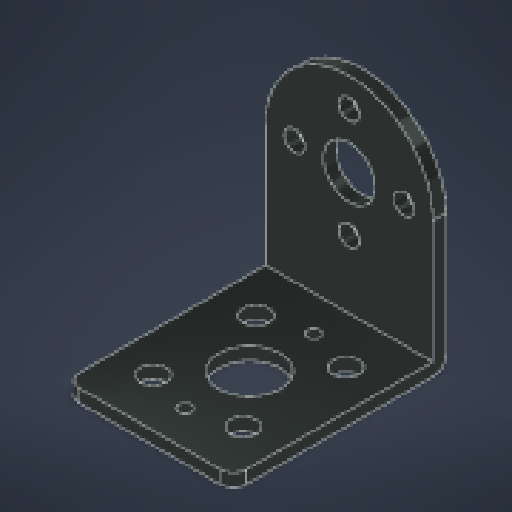
# Autodesk Inventor part: motor holder
Saved by Autodesk Inventor 2026.1 (Build 301233020, 233B)
## iProperties
Created: 2026-02-16
Part Number: motor holder
Material: Steel, Carbon
Document SubType Name: Modeling
Designer: Omar Kashef
Density: 7.85 g/cm^3
Appearance: Gunmetal - Polished
Author: Omar Kashef
Autodesk Inventor part; units mm, degrees
ref_plane "YZ Plane" through (0, 0, 0) normal (1, 0, 0) x (0, 1, 0)
ref_plane "XZ Plane" through (0, 0, 0) normal (0, 1, 0) x (-1, 0, 0)
ref_plane "XY Plane" through (0, 0, 0) normal (0, 0, 1) x (1, 0, 0)
sketch "Sketch1" plane through (0, 0, 0) normal (0, 1, 0) x (-1, 0, 0)
  line L0 (13, 15.5) -> (-13, 15.5)
  line L1 (-13, 15.5) -> (-13, -15.5)
  line L2 (-13, -15.5) -> (13, -15.5)
  line L3 (13, -15.5) -> (13, 15.5)
  line L4 (13, 15.5) -> (-13, -15.5) construction
  line L5 (-13, 15.5) -> (13, -15.5) construction
  circle A0 centre (0, 0) radius 4.8
  line L6 (13, -15.5) -> (-13, -15.5)
  line L7 (-13, -15.5) -> (-13, -17.5)
  line L8 (-13, -17.5) -> (13, -17.5)
  line L9 (13, -17.5) -> (13, -15.5)
  line L10 (-7, 8) -> (7, 8) construction
  line L11 (7, 8) -> (7, -8) construction
  line L12 (7, -8) -> (-7, -8) construction
  line L13 (-7, -8) -> (-7, 8) construction
  line L14 (-7, 8) -> (7, -8) construction
  line L15 (7, 8) -> (-7, -8) construction
  circle A1 centre (7, 8) radius 2
  circle A2 centre (7, -8) radius 2
  circle A3 centre (-7, -8) radius 2
  circle A4 centre (-7, 8) radius 2
  line L16 (0, 0) -> (0, 10) construction
  circle A5 centre (0, 10) radius 1
  line L17 (0, 0) -> (5.5, 0) construction
  circle A6 centre (0, -10) radius 1
  dimension "d0" = 26
  dimension "d1" = 31
  dimension "d2" = 9.6
  dimension "d3" = 15.5
  dimension "d4" = 2
  dimension "d5" = 26
  dimension "d6" = 14
  dimension "d7" = 16
  dimension "d8" = 4
  dimension "d9" = 2
  dimension "d10" = 10
  constraints: 36 end point, 7 centre point, 6 coincident, 6 parallel, 4 horizontal, 4 midpoint, 4 perpendicular, 3 equal radius, 1 symmetric about line, 1 other
  measures "d0" distance of L2.end L1.end
  measures "d1" distance of L1.end L0.end
  measures "d2" diameter of A0
  measures "d3" distance from line of L2 L16.start
  measures "d4" distance of L7.end L6.end
  measures "d5" distance of L7.end L8.end
  measures "d6" distance of L11.end L12.end
  measures "d7" distance of L10.end L11.end
  measures "d8" diameter of A1
  measures "d9" diameter of A5
  measures "d10" distance of L16.start L16.end
extrude "Extrusion1" add sketch "Sketch1" along normal blind 2 contours L3 L2 L1 L0
extrude "Extrusion2" add sketch "Sketch1" along normal blind 34 contours L9 L8 L7 L2
sketch "Sketch2" plane through (-13, 2, -15.5) normal (0, 0, 1) x (1, 0, 0)
  circle A0 centre (13, 19) radius 4
  line L0 (0, 0) -> (0, 32) projected
  line L1 (0, -2) -> (26, -2) projected
  line L2 (0, 32) -> (26, 32) projected
  line L3 (26, 0) -> (26, 32) projected
  arc A1 (26, 19) -> (0, 19) centre (13, 19) ccw
  line L4 (13, 19) -> (13, 27.5) construction
  circle A2 centre (13, 27.5) radius 1.6
  circle A3 centre (4.5, 19) radius 1.6
  circle A4 centre (13, 10.5) radius 1.6
  circle A5 centre (21.5, 19) radius 1.6
  point P0 (13, -2)
  point P1 (13, 32)
  dimension "d15" = 8
  dimension "d16" = 21
  dimension "d17" = 13
  dimension "d18" = 13
  dimension "d19" = 8.5
  dimension "d20" = 3.2
  dimension "d23" = 360
  constraints: 6 centre point, 2 coincident, 2 end point, 2 point on circle, 2 point on line, 1 vertical, 9 other
  measures "d15" diameter of A0
  measures "d16" distance from line of L1 A0.centre
  measures "d17" distance from line of L0 A0.centre
  measures "d18" radius of A1
  measures "d19" distance of L4.start L4.end
  measures "d20" diameter of A2
extrude "Extrusion3" cut sketch "Sketch2" against normal blind 34
fillet "Fillet1" radius 2 1 edges at (0, 0, -17.5)
fillet "Fillet2" radius 2 2 edges at (13, 1, 15.5) (-13, 1, 15.5)
body "Solid1"
